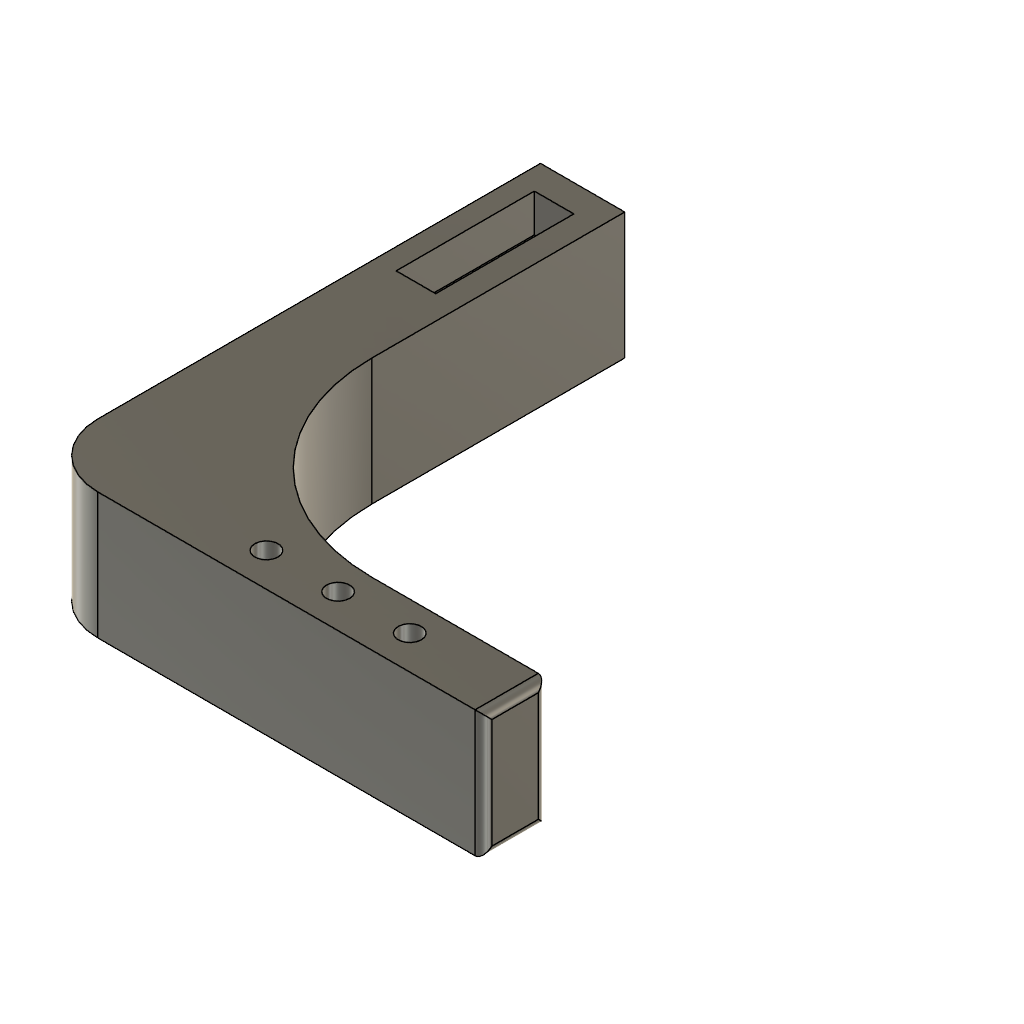
Load_Cell_Stand (Autodesk Fusion 360 design; units mm, degrees)
Autodesk Fusion 360 part; units mm, degrees
sketch "Sketch1" plane through (0, 0, 0) normal (0, 0, 1) x (1, 0, 0)
  line L0 (106.4873, 0) -> (106.4873, 15)
  line L1 (0, 120) -> (0, 0)
  line L2 (0, 120) -> (20, 120)
  line L3 (20, 120) -> (20, 15)
  line L4 (0, 0) -> (106.4873, 0)
  line L5 (106.4873, 15) -> (20, 15)
  constraint vertical L1
  constraint perpendicular L1 L2
  constraint perpendicular L2 L3
  constraint perpendicular L0 L4
  constraint coincident L1.end L4.start
  constraint perpendicular L3 L5
extrude "Extrude1" add sketch "Sketch1" along normal blind 30
sketch "Sketch3" plane through (0, 120, 0) normal (0, 1, 0) x (-1, 0, 0)
  line L0 (-3, 7) -> (-17, 7)
  line L1 (-17, 7) -> (-17, 21)
  line L2 (-17, 21) -> (-3, 21)
  line L3 (-3, 21) -> (-3, 7)
  line L4 (-3, 7) -> (-17, 21) construction
  line L5 (-17, 7) -> (-3, 21) construction
  line L6 (-20, 0) -> (0, 0)
  line L7 (0, 0) -> (0, 30)
  line L8 (0, 30) -> (-20, 30)
  line L9 (-20, 30) -> (-20, 0)
  point P0 (-10, 14)
  dimension "d28" = 14
  dimension "d29" = 14
  constraint horizontal L0
  constraint perpendicular L0 L1
  constraint parallel L0 L2
  constraint parallel L1 L3
  constraint coincident L4 P0
  constraint coincident L5 P0
  measures "d28" distance of L1.end L2.end
  measures "d29" distance of L0.end L1.end
extrude "Extrude2" cut sketch "Sketch3" against normal blind 30 contours L0 L1 L2 L3
sketch "Sketch4" plane through (0, 0, 30) normal (0, 0, 1) x (-1, 0, 0)
  line L0 (-4.9808, -113.5492) -> (-14.3518, -113.5492)
  line L1 (-14.3518, -113.5492) -> (-14.3518, -80.795)
  line L2 (-14.3518, -80.795) -> (-4.9808, -80.795)
  line L3 (-4.9808, -80.795) -> (-4.9808, -113.5492)
  line L4 (-106.4873, 0) -> (-106.4873, -15)
  line L5 (0, -120) -> (0, 0)
  line L6 (0, 0) -> (-106.4873, 0)
  line L7 (-106.4873, -15) -> (-20, -15)
  line L8 (-20, -15) -> (-20, -120)
  line L9 (-20, -120) -> (0, -120)
  constraint horizontal L0
  constraint vertical L1
  constraint horizontal L2
  constraint vertical L3
extrude "Extrude3" cut sketch "Sketch4" against normal up to surface (30 mm away) contours L0 L1 L2 L3
sketch "Sketch6" plane through (0, 0, 30) normal (0, 0, 1) x (-1, 0, 0)
  circle A0 centre (-81, -8) radius 3.7
  circle A1 centre (-64, -8) radius 3.7
  circle A2 centre (-47, -8) radius 3.7
  dimension "d19" = 34
  dimension "d20" = 0
hole "Hole1" at (81, 8, 30) at (64, 8, 30) at (47, 8, 30) direction (0, 0, -1) diameter 5.5 end through all
fillet "Fillet1" radius 45 1 edges at (20, 15, 15)
fillet "Fillet2" radius 15 1 edges at (0, 0, 15)
fillet "Fillet3" radius 2 4 edges at (106.4873, 15, 15) (106.4873, 7.5, 30) (106.4873, 0, 15) (106.4873, 7.5, 0)
equation "d28 = d29"
